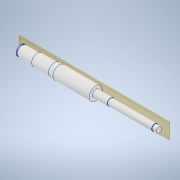
# Autodesk Inventor part: 1.1_3_Shaft_A
Saved by Autodesk Inventor 2021 (Build 250183000, 183)
## iProperties
Created: 2025-11-13
Part Number: 1.1_3_Shaft_A
Material: Aluminum 6061
Document SubType Name: Modeling
Designer: Admin
Density: 2.7 g/cm^3
Appearance: Aluminum - Flat
Mass: 77.4973 g
Surface Area: 87.0566 cm^2
Volume: 28.7027 cm^3
Author: Admin
Autodesk Inventor part; units mm, degrees
ref_plane "YZ Plane" through (0, 0, 0) normal (1, 0, 0) x (0, 1, 0)
ref_plane "XZ Plane" through (0, 0, 0) normal (0, 1, 0) x (-1, 0, 0)
sketch "Sketch1" plane through (0, 0, 0) normal (0, 1, 0) x (-1, 0, 0)
  line L0 (-25, 0) -> (-25, 4)
  line L1 (-25, 4) -> (-19, 4)
  line L2 (64, 5) -> (64, 9.2)
  line L3 (64, 9.2) -> (115, 9.2)
  line L4 (168.1, 7) -> (169, 7)
  line L5 (169, 7) -> (169, 0)
  line L6 (169, 0) -> (-25, 0)
  line L7 (167, 7) -> (167, 6.7)
  line L8 (167, 6.7) -> (168.1, 6.7)
  line L9 (168.1, 6.7) -> (168.1, 7)
  line L10 (207.8, 0) -> (-63.8, 0) projected
  line L11 (0, -1.84) -> (0, 11.04) projected
  line L12 (115, 9.2) -> (115, 8.5)
  line L13 (115, 8.5) -> (122, 8.5)
  line L14 (167, 7) -> (146, 7)
  line L15 (146, 7) -> (146, 8)
  line L16 (146, 8) -> (122, 8)
  line L17 (122, 8.5) -> (122, 8)
  line L18 (-19, 4) -> (-19, 4.5)
  line L19 (-19, 4.5) -> (43, 4.5)
  line L20 (43, 4.5) -> (43, 5)
  line L21 (43, 5) -> (64, 5)
  dimension "d4" = 4
  dimension "d5" = 6
  dimension "d9" = 9.2
  dimension "d11" = 0.9
  dimension "d12" = 1.1
  dimension "d15" = 25
  dimension "d16" = 8.5
  dimension "d18" = 7
  dimension "d21" = 7
  dimension "d23" = 45
  dimension "d24" = 21
  dimension "d25" = 8
  dimension "d26" = 6.7
  dimension "d39" = 5
  dimension "d40" = 4.5
  dimension "d41" = 83
  dimension "d42" = 21
  dimension "d43" = 51
  constraints: 41 end point, 10 perpendicular, 4 vertical, 2 collinear, 2 horizontal
  measures "d4" distance between parallel lines of L6 L1
  measures "d5" distance of L0.end L1.end
  measures "d9" distance between parallel lines of L6 L3
  measures "d11" distance of L4.start L4.end
  measures "d12" distance of L7.end L8.end
  measures "d15" distance between parallel lines of L11 L0
  measures "d16" distance between parallel lines of L10 L13
  measures "d18" distance of L12.end L13.end
  measures "d21" distance between parallel lines of L10 L14
  measures "d23" distance between parallel lines of L7 L17
  measures "d24" distance of L7.start L14.end
  measures "d25" distance between parallel lines of L6 L16
  measures "d26" distance between parallel lines of L8 L10
  measures "d39" distance between parallel lines of L10 L21
  measures "d40" distance between parallel lines of L6 L19
  measures "d41" distance between parallel lines of L18 L2
  measures "d42" distance of L20.end L2.start
  measures "d43" distance between parallel lines of L12 L2
revolve "Revolution1" add sketch "Sketch1" angle 360 about axis through (-169, 0, 0) along (1, 0, 0)
fillet "Fillet1" radius 0.2 1 edges at (-115, 0, -8.5)
fillet "Fillet2" radius 0.2 1 edges at (19, 0, -4)
ref_plane "Work Plane1" through (-53.5, 0, -5) normal (0, 0, 1) x (1, 0, 0)
sketch "Sketch2" plane through (-53.5, 0, -5) normal (0, 0, 1) x (1, 0, 0)
  line L0 (6.5, 0) -> (-6.5, 0) construction
  line L1 (6.5, 1.5) -> (-6.5, 1.5)
  line L2 (-6.5, -1.5) -> (6.5, -1.5)
  arc A0 (6.5, -1.5) -> (6.5, 1.5) centre (6.5, 0) ccw
  arc A1 (-6.5, 1.5) -> (-6.5, -1.5) centre (-6.5, 0) ccw
  line L3 (-10.5, -9.2) -> (-10.5, 9.2) projected
  point P0 (53.5, 0)
  point P1 (0, 0)
  point P2 (-10.5, 0)
  dimension "d29" = 3
  dimension "d30" = 10.5
  dimension "d31" = 13
  constraints: 8 end point, 4 point on circle, 4 tangent, 2 centre point, 2 midpoint, 1 horizontal, 1 parallel, 1 point on line
  measures "d29" distance between parallel lines of L2 L1
  measures "d30" distance from line of L3 point (0, 0)
  measures "d31" distance of L1.start L1.end
extrude "Extrusion1" [suppressed]
ref_plane "Work Plane2" through (-156.5, 0, -7) normal (0, 0, 1) x (1, 0, 0)
sketch "Sketch3" plane through (-156.5, 0, -7) normal (0, 0, 1) x (1, 0, 0)
  line L0 (5.5, 0) -> (-5.5, 0) construction
  line L1 (5.5, 2.5) -> (-5.5, 2.5)
  line L2 (-5.5, -2.5) -> (5.5, -2.5)
  arc A0 (5.5, -2.5) -> (5.5, 2.5) centre (5.5, 0) ccw
  arc A1 (-5.5, 2.5) -> (-5.5, -2.5) centre (-5.5, 0) ccw
  line L3 (-10.5, -7) -> (-10.5, 7) projected
  point P0 (156.5, 0)
  point P1 (0, 0)
  point P2 (-10.5, 0)
  dimension "d34" = 10.5
  dimension "d35" = 5
  dimension "d36" = 11
  constraints: 8 end point, 4 point on circle, 4 tangent, 2 centre point, 2 midpoint, 1 horizontal, 1 parallel, 1 point on line
  measures "d34" distance from line of L3 point (0, 0)
  measures "d35" distance between parallel lines of L1 L2
  measures "d36" distance of L0.start L0.end
extrude "Extrusion2" [suppressed]
body "Solid1"
